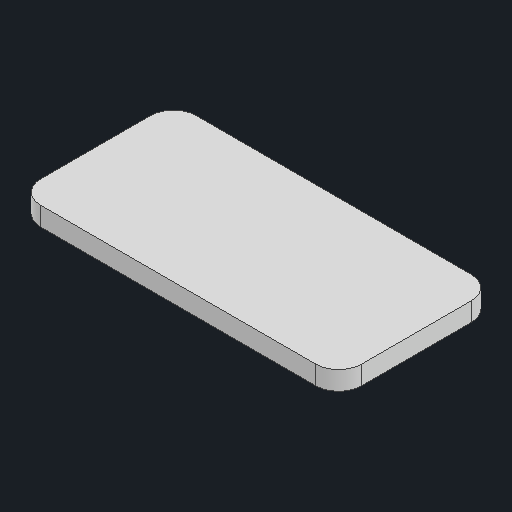
# Autodesk Inventor part: phone
Saved by Autodesk Inventor 2027 (Build 310192060, 192F)
## iProperties
Created: 2026-08-21
Part Number: phone
Material: Generic
Document SubType Name: Modeling
Designer: Aiden
Density: 1 g/cm^3
Appearance: Default
Author: Aiden
Autodesk Inventor part; units mm, degrees
ref_plane "YZ Plane" through (0, 0, 0) normal (1, 0, 0) x (0, 1, 0)
ref_plane "XZ Plane" through (0, 0, 0) normal (0, 1, 0) x (-1, 0, 0)
ref_plane "XY Plane" through (0, 0, 0) normal (0, 0, 1) x (1, 0, 0)
sketch "Sketch1" plane through (0, 0, 0) normal (0, 1, 0) x (-1, 0, 0)
  line L0 (0, 0) -> (147.574, 0)
  line L1 (147.574, 0) -> (147.574, -71.501)
  line L2 (147.574, -71.501) -> (0, -71.501)
  line L3 (0, -71.501) -> (0, 0)
  dimension "d0" = 147.574
  dimension "d1" = 71.501
  constraints: 8 end point, 2 parallel, 1 horizontal, 1 perpendicular
  measures "d0" distance of L1.end L2.end
  measures "d1" distance of L0.end L1.end
extrude "Extrusion1" add sketch "Sketch1" along normal blind 8.6487
fillet "Fillet1" radius 10.5 4 edges at (0, 4.3243, 0) (0, 4.3243, -71.501) (-147.574, 4.3243, -71.501) (-147.574, 4.3243, 0)
sketch "Sketch2" plane through (0, 0, 0) normal (0, -1, 0) x (1, 0, 0)
  line L0 (-143.0147, -66.9417) -> (-102.5398, -66.9417)
  line L1 (-102.5398, -66.9417) -> (-102.5398, -29.1084)
  line L2 (-102.5398, -29.1084) -> (-143.0147, -29.1084)
  line L3 (-143.0147, -29.1084) -> (-143.0147, -66.9417)
  line L4 (-10.5, -71.501) -> (-137.074, -71.501) projected
  line L5 (-147.574, -61.001) -> (-147.574, -10.5) projected
  point P0 (0, 0)
  dimension "d5" = 37.8333
  dimension "d6" = 40.4749
  dimension "d7" = 4.5593
  dimension "d8" = 4.5593
  constraints: 8 end point, 2 parallel, 1 horizontal, 1 perpendicular
  measures "d5" distance of L2.end L0.start
  measures "d6" distance of L1.end L2.end
  measures "d7" distance between parallel lines of L4 L0
  measures "d8" distance between parallel lines of L5 L3
extrude "Extrusion2" add sketch "Sketch2" along normal blind 4.2164
fillet "Fillet2" radius 10.5 4 edges at (-143.0147, -2.1082, -66.9417) (-143.0147, -2.1082, -29.1084) (-102.5398, -2.1082, -29.1084) (-102.5398, -2.1082, -66.9417)
body "Solid1"
